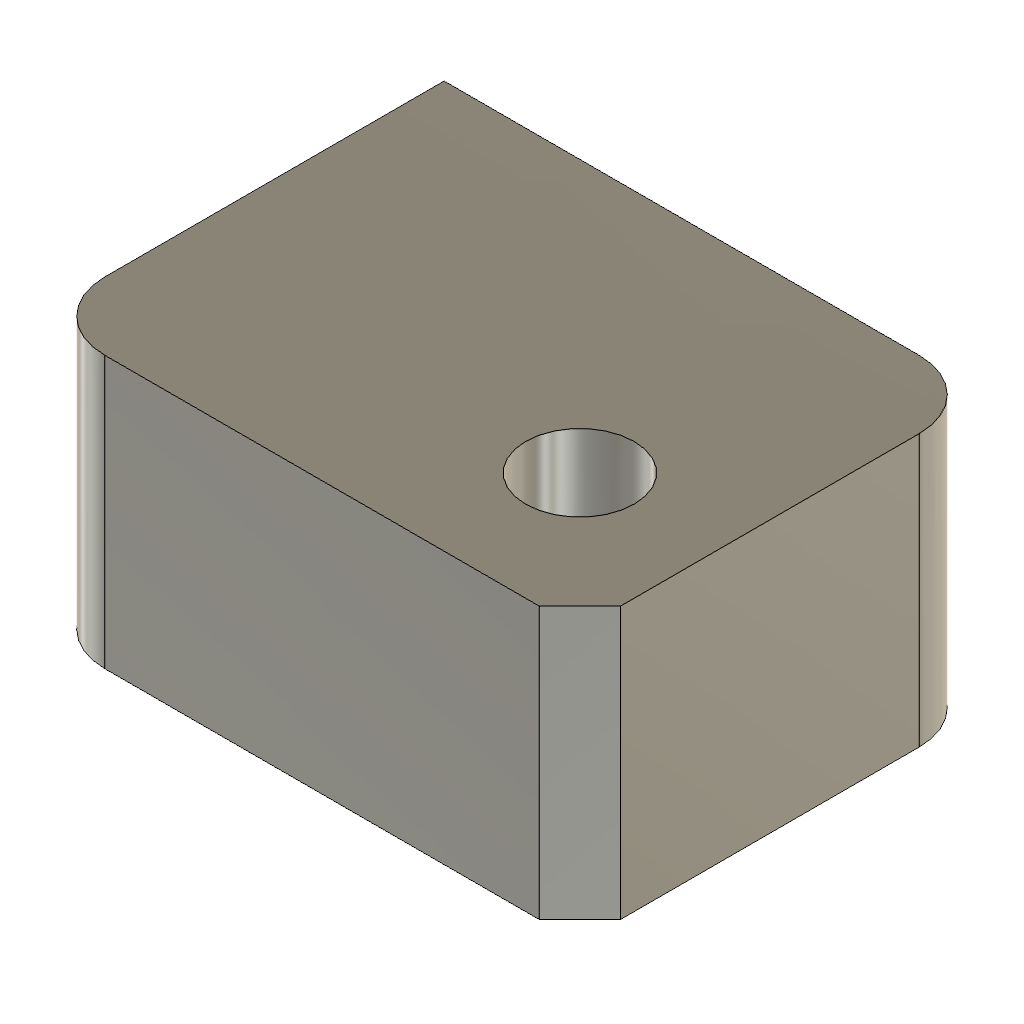
vendor_CornerSetPart (Autodesk Fusion 360 design; units mm, degrees)
Autodesk Fusion 360 part; units mm, degrees
sketch "Base sketch" plane through (0, 0, 0) normal (0, 0, 1) x (1, 0, 0)
  line L0 (0, 0) -> (40, 0)
  line L1 (40, 0) -> (40, 30)
  line L2 (40, 30) -> (0, 30)
  line L3 (0, 30) -> (0, 0)
extrude "Base extrude" add sketch "Base sketch" along normal blind 20
hole "Side hole" at (30, 10, 20) direction (0, 0, -1) diameter 8 end through all
fillet "Corner rounds" radius 5 2 edges at (40, 30, 10) (0, 0, 10)
chamfer "Corner bevel" distance 3 angle 45 1 edges at (40, 0, 10) measured on face at (16.6667, 0, 13.3333) tangent chain off
equation "height = 20.0 mm"
